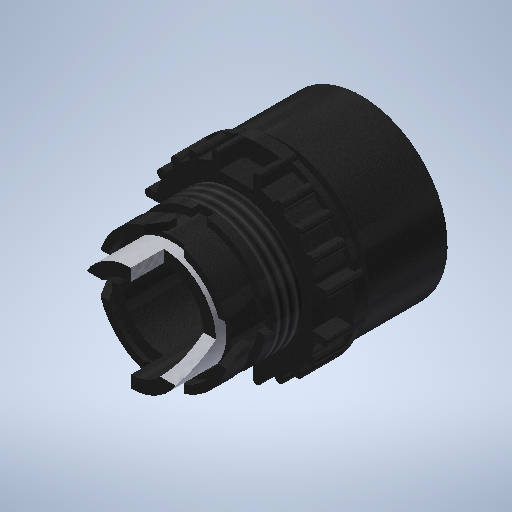
# Autodesk Inventor part: BOTAO1
Saved by Autodesk Inventor 2025 (Build 290162000, 162)
## iProperties
Created: 2015-03-23
Part Number: BOTAO1
Material: PCL plástico
Document SubType Name: Modeling
Designer: cliente
Density: 1.626 g/cm^3
Appearance: Preto moldado(2)
Mass: 20.0841 g
Surface Area: 68.4591 cm^2
Volume: 12.3518 cm^3
Author: cliente
Autodesk Inventor part; units mm, degrees
ref_plane "YZ Plane" through (0, 0, 0) normal (1, 0, 0) x (0, 1, 0)
ref_plane "XZ Plane" through (0, 0, 0) normal (0, 1, 0) x (-1, 0, 0)
ref_plane "XY Plane" through (0, 0, 0) normal (0, 0, 1) x (1, 0, 0)
sketch "Esboço1" plane through (0, 0, 0) normal (1, 0, 0) x (0, 1, 0)
  line L0 (2.7, 0) -> (-0.6, 0)
  line L1 (-0.6, -6.5) -> (-37.6, -6.5)
  line L2 (-37.6, -6.5) -> (-37.6, -8.5)
  line L3 (-37.6, -8.5) -> (-32.3, -8.5)
  line L4 (-32.3, -8.5) -> (-32.3, -10.75)
  line L5 (-32.3, -10.75) -> (-28.8, -10.75)
  line L6 (-28.8, -10.75) -> (-28.8, -9.5)
  line L7 (-26.5, -9.5) -> (-26.5, -10.75)
  line L8 (-26.5, -10.75) -> (-20.5, -10.75)
  line L9 (-20.5, -10.75) -> (-20.5, -13.6)
  line L10 (-20.5, -13.6) -> (-15.5, -13.6)
  line L11 (-15.5, -13.6) -> (-15.5, -14.75)
  line L12 (-15.5, -14.75) -> (-14.5, -14.75)
  line L13 (-14.5, -14.75) -> (-14.5, -11.1125)
  line L14 (-14.5, -11.1125) -> (-13, -11.1125)
  line L15 (-13, -11.1125) -> (-13, -14)
  line L16 (-13, -14) -> (-0.2, -14)
  arc A0 (-0.2, -14) -> (0, -11.5) centre (-19.99708, -11.158234) ccw
  line L17 (-26.5, -9.5) -> (-28.8, -9.5)
  line L18 (0, -11.5) -> (-0.3, -11.5)
  line L19 (-0.3, -11.5) -> (-0.3, -11.45)
  line L20 (-0.3, -11.45) -> (0, -11.45)
  arc A1 (0, -11.45) -> (3, -4.308572) centre (-7, -4.308572) ccw
  line L21 (3, -4.308572) -> (3, -4)
  arc A2 (2.7, 0) -> (3, -4) centre (29.516667, 0) ccw
  line L22 (-0.6, -6.5) -> (-0.6, 0)
  point P0 (0, 0)
  point P1 (1.05, 0)
  dimension "d1" = 28
  dimension "d2" = 22.225
  dimension "d3" = 13
  dimension "d4" = 17
  dimension "d5" = 21.5
  dimension "d6" = 19
  dimension "d7" = 27.2
  dimension "d8" = 29.5
  dimension "d11" = 1.5
  dimension "d12" = 1
  dimension "d13" = 6
  dimension "d14" = 6
  dimension "d15" = 2.3
  dimension "d16" = 3.5
  dimension "d17" = 5.3
  dimension "d19" = 23
  dimension "d22" = 0.3
  dimension "d24" = 0.2
  dimension "d25" = 13
  dimension "d26" = 22.9
  dimension "d27" = 3
  dimension "d28" = 0.3
  dimension "d29" = 10
  dimension "d30" = 20
  dimension "d31" = 8
  dimension "d110" = 37
  constraints: 46 end point, 13 perpendicular, 6 point on circle, 3 centre point, 3 horizontal, 3 vertical, 2 horizontal alignment, 2 point on line, 2 vertical alignment, 1 midpoint, 1 parallel, 1 tangent
  measures "d1" diameter of L16 L0
  measures "d2" diameter of L14 L0
  measures "d3" diameter of L1 L0
  measures "d4" diameter of L3 L0
  measures "d5" diameter of L5 L0
  measures "d6" diameter of L17 L0
  measures "d7" diameter of L10 L0
  measures "d8" diameter of L12 L0
  measures "d11" distance between parallel lines of L13 L15
  measures "d12" distance of L11.end L12.end
  measures "d13" distance between parallel lines of L9 L13
  measures "d14" distance between parallel lines of L7 L9
  measures "d15" distance between parallel lines of L6 L7
  measures "d16" distance of L4.end L5.end
  measures "d17" distance between parallel lines of L2 L4
  measures "d19" diameter of L18.start L0
  measures "d22" distance of L18.start L18.end
  measures "d24" horizontal distance of L16.end L18.start
  measures "d25" distance from line of L15 L18.start
  measures "d26" diameter of L20 L0
  measures "d27" distance from line of L18.start L21
  measures "d28" distance from line of L0.start L21
  measures "d29" radius of A1
  measures "d30" radius of A0
  measures "d31" diameter of L21.end L0
  measures "d110" distance between parallel lines of L2 L22
revolve "Revolução1" add sketch "Esboço1" angle 360 about axis through (0, 2.7, 0) along (0, -1, 0)
sketch "Esboço10" plane through (0, 0, 0) normal (1, 0, 0) x (0, 1, 0)
  line L0 (-32.3, 10.75) -> (-32.3, -10.75)
  line L1 (-32.3, 8.5) -> (-37.6, 8.5)
  line L2 (-37.6, 6.5) -> (-37.6, -6.5)
  line L3 (-37.6, 8.5) -> (-37.6, -4.447228)
  line L4 (-37.6, 8.5) -> (-37.6, -8.5)
  line L5 (-37.6, -4.447228) -> (-32.3, 0)
  line L6 (-32.3, 0) -> (-32.3, 8.5)
  line L7 (-32.3, 8.5) -> (-37.6, 8.5)
  point P0 (0, 0)
  dimension "d104" = 130
  constraints: 8 end point, 1 collinear, 1 midpoint, 1 perpendicular, 1 point on line
  measures "d104" angle of L0 L5
extrude "Extrusão7" cut sketch "Esboço10" along normal through all
pattern_circular "Padrão circular2" count 2 over 360 about axis through (0, -10, 0) along (0, 1, 0) of "Extrusão7"
sketch "Esboço5" plane through (0, -32.3, 0) normal (0, -1, 0) x (1, 0, 0)
  circle A0 centre (0, 0) radius 9.5
  line L0 (-10.677078, -1.25) -> (-9.417404, -1.25)
  line L1 (9.417404, -1.25) -> (10.677078, -1.25)
  line L2 (10.677078, 1.25) -> (9.417404, 1.25)
  line L3 (-9.417404, 1.25) -> (-10.677078, 1.25)
  line L4 (-1.25, -10.677078) -> (-1.25, -9.417404)
  line L5 (-1.25, 9.417404) -> (-1.25, 10.677078)
  line L6 (1.25, 10.677078) -> (1.25, 9.417404)
  line L7 (1.25, -9.417404) -> (1.25, -10.677078)
  arc A1 (-1.25, -9.417404) -> (1.25, -9.417404) centre (0, 0) ccw
  arc A2 (9.417404, -1.25) -> (9.417404, 1.25) centre (0, 0) ccw
  arc A3 (1.25, 9.417404) -> (-1.25, 9.417404) centre (0, 0) ccw
  arc A4 (-9.417404, 1.25) -> (-9.417404, -1.25) centre (0, 0) ccw
  arc A5 (-1.25, -10.677078) -> (1.25, -10.677078) centre (0, 0) ccw
  arc A6 (-10.677078, 1.25) -> (-10.677078, -1.25) centre (0, 0) ccw
  arc A7 (10.677078, -1.25) -> (10.677078, 1.25) centre (0, 0) ccw
  arc A8 (1.25, 10.677078) -> (-1.25, 10.677078) centre (0, 0) ccw
  point P0 (0, 0)
  point P1 (-1.25, 10.047241)
  point P2 (-1.25, -10.047241)
  point P3 (1.25, -10.047241)
  point P4 (1.25, 10.047241)
  point P5 (-10.047241, -1.25)
  point P6 (10.047241, -1.25)
  point P7 (10.047241, 1.25)
  point P8 (-10.047241, 1.25)
  dimension "d51" = 10.75
  dimension "d52" = 2.5
  dimension "d53" = 2.5
  dimension "d54" = 1.25
  dimension "d55" = 1.25
  constraints: 16 end point, 16 point on circle, 8 centre point, 8 midpoint, 8 parallel, 3 concentric, 2 horizontal, 2 horizontal alignment, 2 vertical alignment, 1 coincident, 1 vertical, 13 other
  measures "d51" radius of A5
  measures "d52" distance between parallel lines of L5 L6
  measures "d53" distance between parallel lines of L3 L0
  measures "d54" distance from line of point (0, 0) L0
  measures "d55" distance from line of point (0, 0) L5
extrude "Extrusão3" cut sketch "Esboço5" against normal blind 7 contours A0 L2 A7 L1 | A0 L5 A8 L6 | L7 A5 L4 A0 | A0 L0 A6 L3
chamfer "Chanfro1" distance 2 angle 45 8 edges at (-1.25, -32.3, 10.0472) (1.25, -32.3, 10.0472) (10.0472, -32.3, 1.25) (10.0472, -32.3, -1.25) (-10.0472, -32.3, 1.25) (-10.0472, -32.3, -1.25) (-1.25, -32.3, -10.0472) (1.25, -32.3, -10.0472)
sketch "Esboço6" plane through (0, 0, 0) normal (1, 0, 0) x (0, 1, 0)
  line L0 (0, 0) -> (-32.3, 0)
  line L1 (-32.3, -8.5) -> (-37.6, -8.5)
  line L2 (-25.3, -9.5) -> (-32.3, -9.5)
  line L3 (-32.3, -9.5) -> (-32.3, -8.5)
  line L4 (-32.3, -3.25) -> (-32.3, -10.246951)
  line L5 (-32.3, -9.5) -> (-30.8, -9.5)
  line L6 (-30.8, -9.5) -> (-30.8, -8.7)
  line L7 (-30.8, -8.7) -> (-27.3, -8.7)
  line L8 (-27.3, -8.7) -> (-27.3, -8.5)
  line L9 (-27.3, -8.5) -> (-32.3, -8.5)
  point P0 (-32.3, -9)
  dimension "d61" = 1.5
  dimension "d62" = 5
  dimension "d63" = 0.2
  constraints: 14 end point, 3 perpendicular, 1 collinear, 1 horizontal, 1 midpoint, 1 point on line, 1 vertical, 1 vertical alignment
  measures "d61" distance between parallel lines of L3 L6
  measures "d62" distance between parallel lines of L4 L8
  measures "d63" distance between parallel lines of L9 L7
revolve "Revolução2" cut sketch "Esboço6" angle 360 about axis through (0, 0, 0) along (0, -1, 0)
sketch "Esboço7" plane through (0, -20.5, 0) normal (0, -1, 0) x (1, 0, 0)
  arc A0 (-3.418103, -14.862001) -> (0, -15.25) centre (0, 0) ccw
  line L0 (0, 0) -> (0, -15.25) construction
  arc A1 (-4, -14.131083) -> (-3.418103, -14.862001) centre (-3.25, -14.131083) ccw
  line L1 (-4, -14.131083) -> (-4, -13.181806)
  arc A2 (-7.649519, -11.749356) -> (-6.350481, -12.499356) centre (-7, -12.124356) ccw
  line L2 (-7, -12.124356) -> (0, 0) construction
  line L3 (0, 0) -> (-9.899495, -9.899495) construction
  line L4 (0, 0) -> (-12.124356, -7) construction
  arc A3 (-10.429825, -9.369165) -> (-9.369165, -10.429825) centre (-9.899495, -9.899495) ccw
  arc A4 (-12.499356, -6.350481) -> (-11.749356, -7.649519) centre (-12.124356, -7) ccw
  line L5 (-6.350481, -12.499356) -> (-6.257407, -12.338147)
  line L6 (-7.649519, -11.749356) -> (-7.556445, -11.588147)
  line L7 (-9.369165, -10.429825) -> (-9.237538, -10.298198)
  line L8 (-10.429825, -9.369165) -> (-10.298198, -9.237538)
  line L9 (-11.749356, -7.649519) -> (-11.588147, -7.556445)
  line L10 (-12.499356, -6.350481) -> (-12.338147, -6.257407)
  circle A5 centre (0, 0) radius 14.75 construction
  arc A6 (-4, -13.181806) -> (-4.173285, -12.943867) centre (-4.25, -13.181806) ccw
  arc A7 (-5.931859, -12.23818) -> (-6.257407, -12.338147) centre (-6.0409, -12.463147) ccw
  arc A8 (-7.556445, -11.588147) -> (-7.632645, -11.256231) centre (-7.772951, -11.463147) ccw
  arc A9 (-8.89721, -10.285896) -> (-9.237538, -10.298198) centre (-9.060761, -10.474975) ccw
  arc A10 (-10.298198, -9.237538) -> (-10.285896, -8.89721) centre (-10.474975, -9.060761) ccw
  arc A11 (-11.256231, -7.632645) -> (-11.588147, -7.556445) centre (-11.463147, -7.772951) ccw
  arc A12 (-12.338147, -6.257407) -> (-12.23818, -5.931859) centre (-12.463147, -6.0409) ccw
  arc A13 (-5.931859, -12.23818) -> (-4.173285, -12.943867) centre (0, 0) ccw
  arc A14 (-8.89721, -10.285896) -> (-7.632645, -11.256231) centre (0, 0) ccw
  arc A15 (-11.256231, -7.632645) -> (-10.285896, -8.89721) centre (0, 0) ccw
  line L11 (0, 0) -> (-15.25, 0) construction
  line L12 (-13.181806, -4) -> (-14.131083, -4)
  arc A16 (-15.25, 0) -> (-14.862001, -3.418103) centre (0, 0) ccw
  arc A17 (-14.862001, -3.418103) -> (-14.131083, -4) centre (-14.131083, -3.25) ccw
  arc A18 (-12.943867, -4.173285) -> (-12.23818, -5.931859) centre (0, 0) ccw
  arc A19 (-12.943867, -4.173285) -> (-13.181806, -4) centre (-13.181806, -4.25) ccw
  arc A20 (-13, 0) -> (0, -13) centre (0, 0) ccw
  line L13 (0, -13) -> (0, -15.25)
  line L14 (-13, 0) -> (-15.25, 0)
  circle A21 centre (0, 0) radius 13.6 construction
  circle A22 centre (0, 0) radius 13.6 construction
  circle A23 centre (0, 0) radius 14.75 construction
  point P0 (-12.998461, -4)
  point P1 (-14.716063, -4)
  dimension "d65" = 30.5
  dimension "d67" = 1.5
  dimension "d68" = 4
  dimension "d70" = 15
  dimension "d71" = 15
  dimension "d72" = 30
  dimension "d73" = 0.5
  dimension "d74" = 4
  dimension "d76" = 0.75
  dimension "d77" = 0.25
  dimension "d78" = 26
  constraints: 42 point on circle, 30 end point, 30 tangent, 22 centre point, 15 equal radius, 7 coincident, 6 parallel, 5 concentric, 4 point on line, 2 collinear, 2 vertical, 1 horizontal, 1 perpendicular
  measures "d65" diameter of A0
  measures "d67" diameter of A1
  measures "d68" distance between parallel lines of L0 L1
  measures "d70" angle of L3 L2
  measures "d71" angle of L4 L3
  measures "d72" angle of L0 L2
  measures "d73" diameter of A6
  measures "d74" distance between parallel lines of L11 L12
  measures "d76" radius of A17
  measures "d77" radius of A19
  measures "d78" diameter of A20
extrude "Extrusão4" add sketch "Esboço7" against normal up to surface (6 mm away)
sketch "Esboço8" plane through (-15.25, -20.5, 0) normal (0, -1, 0) x (1, 0, 0)
  line L0 (15.25, -15.25) -> (15.25, -12.25)
  line L1 (15.25, -13.6) -> (15.25, -14.75)
  line L2 (15.25, -12.25) -> (12.5, -12.25)
  arc A0 (11.889831, -14.875206) -> (15.25, -15.25) centre (15.25, 0) ccw
  arc A1 (11.831897, -14.862001) -> (15.25, -15.25) centre (15.25, 0) ccw construction
  line L3 (0, 0) -> (3, 0)
  line L4 (0, 0) -> (1.65, 0)
  line L5 (3, 0) -> (3, -2.75)
  arc A2 (0, 0) -> (0.387999, -3.418103) centre (15.25, 0) ccw construction
  line L6 (12.5, -12.25) -> (12.5, -14.387495)
  arc A3 (11.889831, -14.875206) -> (12.5, -14.387495) centre (12, -14.387495) ccw
  line L7 (3, -2.75) -> (0.862505, -2.75)
  arc A4 (0.862505, -2.75) -> (0.374794, -3.360169) centre (0.862505, -3.25) ccw
  arc A5 (0, 0) -> (0.387999, -3.418103) centre (15.25, 0) ccw
  arc A6 (0, 0) -> (0.374794, -3.360169) centre (15.25, 0) ccw
  point P0 (15.25, 0)
  dimension "d83" = 3
  dimension "d84" = 1
  dimension "d85" = 2.75
  dimension "d86" = 3
  dimension "d87" = 2.75
  constraints: 12 end point, 10 point on circle, 4 centre point, 4 tangent, 2 collinear, 2 concentric, 2 perpendicular, 1 equal radius, 1 horizontal
  measures "d83" distance of L0.start L0.end
  measures "d84" diameter of A3
  measures "d85" distance between parallel lines of L0 L6
  measures "d86" distance of L3.start L3.end
  measures "d87" distance between parallel lines of L3 L7
extrude "Extrusão5" cut sketch "Esboço8" against normal blind 4
mirror "Simetria1" about plane through (0, 0, 0) normal (1, 0, 0) of "Extrusão4", "Extrusão5"
mirror "Simetria2" about plane through (0, 0, 0) normal (0, 0, 1) of "Extrusão4", "Extrusão5", "Simetria1"
thread "Rosca1" size "M22x1.5" class "6g" standard "ANSI Metric M Profile" length 10 offset 1.5
